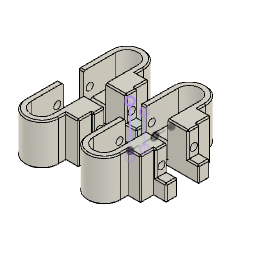
triangle_lab_filament_sensor_mount (Autodesk Fusion 360 design; units mm, degrees)
Autodesk Fusion 360 part; units mm, degrees
sketch "Primary" plane through (0, 0, 0) normal (0, 1, 0) x (1, 0, 0) in component "triangle_lab_filament_sensor_mount_a"
  line L0 (0, 0) -> (16, 0)
  line L1 (16, 0) -> (16, -23.5)
  line L2 (16, -23.5) -> (0, -23.5)
  line L3 (0, -23.5) -> (0, 0)
  line L4 (16, -12) -> (22, -12)
  line L5 (22, -12) -> (22, 0)
  line L6 (22, 0) -> (16, 0)
  line L7 (16, 0) -> (16, -12)
  line L8 (8, -23.5) -> (8, 0) construction
  circle A0 centre (8, -15.5) radius 5.3
  circle A1 centre (8, -15.5) radius 8
  line L9 (22, 0) -> (28, 0)
  line L10 (28, 0) -> (28, -5.6)
  line L11 (28, -5.6) -> (22, -5.6)
  line L12 (22, -5.6) -> (22, 0)
  line L13 (2.7, -15.5) -> (2.7, 0)
  line L14 (13.3, -15.5) -> (13.3, 0)
  line L15 (23, -5.6) -> (23, 0)
  line L16 (8, -20.8) -> (16, -20.8) construction
  line L17 (13.3, -2.8) -> (0, -2.8) construction
  line L18 (2.7, -17.4) -> (13.3, -17.4) construction
  circle A2 centre (8, -17.4) radius 2.1
  circle A3 centre (8, -17.4) radius 4.8
  dimension "d1" = 16
  dimension "d3" = 12
  dimension "d4" = 6
  dimension "d5" = 10.6
  dimension "d6" = 5.6
  dimension "d7" = 6
  dimension "d28" = 9.4
  dimension "d41" = 1
  dimension "d54" = 18
  dimension "d55" = 2.8
  dimension "d57" = 3.4
  dimension "d58" = 4.2
  dimension "d62" = 9.6
  constraint horizontal L0
  constraint vertical L1
  constraint horizontal L2
  constraint vertical L3
  constraint coincident L0.start L3.end
  constraint horizontal L4
  constraint vertical L5
  constraint horizontal L6
  constraint vertical L7
  constraint coincident L1 L4.start
  constraint collinear L0 L6
  constraint midpoint L2 L8.start
  constraint midpoint L0 L8.end
  constraint coincident L8 A0.centre
  constraint tangent L3 A1
  constraint tangent L2 A1
  constraint tangent L1 A1
  constraint horizontal L9
  constraint vertical L10
  constraint horizontal L11
  constraint vertical L12
  constraint coincident A0 L13.start
  constraint coincident L0 L13.end
  constraint tangent A0 L13
  constraint coincident A0 L14.start
  constraint coincident L0 L14.end
  constraint perpendicular L0 L14
  constraint perpendicular L0 L13
  constraint tangent A0 L14
  constraint coincident L11 L15.start
  constraint coincident L9 L15.end
  constraint perpendicular L9 L15
  constraint coincident A0 L16.start
  constraint coincident L8 L16.start
  constraint coincident L1 L16.end
  constraint tangent A0 L16
  constraint coincident A0.centre A1.centre
  constraint coincident L14 L17.start
  constraint coincident L3 L17.end
  constraint perpendicular L3 L17
  constraint coincident L13 L18.start
  constraint coincident L14 L18.end
  constraint perpendicular L14 L18
  constraint midpoint L18 A2.centre
  constraint concentric A2 A3
  measures "d1" distance of L0.start L0.end
  measures "d3" distance of L4.end L5.end
  measures "d4" distance of L5.end L0.end
  measures "d5" diameter of A0
  measures "d6" distance of L9.end L10.end
  measures "d7" distance of L5.end L9.end
  measures "d41" distance of L5 L15
  measures "d54" distance of L16 L17
  measures "d55" distance of L0 L17
  measures "d57" distance of L16 L18
  measures "d58" diameter of A2
  measures "d62" diameter of A3
extrude "Extrude1" add sketch "Primary" along normal blind 20 contours L0 L3 A1 L13 | L0 A1 L13 L14 | A0 A1 L13 L14 A3 | L0 L1 L7 A1 L14 | A0 A1 L13 L14 | L1 L4 L5 L6 L7 L12 | A0 A3 | A0 A3 | A0 A3 | A2 makes body 1 in component "triangle_lab_filament_sensor_mount_a"
extrude "Extrude4" add sketch "Primary" along normal blind 8 contours L5 L9 L11 L12 L15 | L9 L10 L11 L15 bodies 1 in component "triangle_lab_filament_sensor_mount_a"
extrude "Extrude8" add sketch "Primary" along normal up to surface (12 mm away) from surface at 8 contours L5 L9 L11 L12 L15 bodies 1 in component "triangle_lab_filament_sensor_mount_a"
extrude "Extrude2" cut sketch "Primary" along normal up to surface (13 mm away) from surface at 7 contours L0 A1 L13 L14 | A0 A1 L13 L14 | A0 A3 | A0 A3 | A2 picked at (8.6958, -11.0584) picked at (11.7721, -17.7848) bodies 1 in component "triangle_lab_filament_sensor_mount_a"
extrude "Extrude3" cut sketch "Primary" along normal up to surface (7 mm away) contours A2 bodies 1 in component "triangle_lab_filament_sensor_mount_a"
sketch "Sketch4" plane through (0, 0, 0) normal (-1, 0, 0) x (0, -1, 0) in component "triangle_lab_filament_sensor_mount_a"
  line L0 (0, 0) -> (0, 15.5)
  line L1 (0, 15.5) -> (-20, 15.5)
  line L2 (-20, 15.5) -> (-20, 0)
  line L3 (-20, 0) -> (0, 0)
  circle A0 centre (-12, 2.8) radius 1.7
  line L4 (0, 23.5) -> (0, 0)
  line L5 (-7, 15.5) -> (-7, 0)
  line L6 (0, 2.8) -> (-20, 2.8) construction
  point P0 (0, 2.8)
  dimension "d37" = 3.4
  dimension "d40" = 5
  constraint coincident P0 L6.start
  constraint coincident L2 L6.end
  constraint perpendicular L2 L6
  constraint coincident A0.centre L6
  measures "d37" diameter of A0
  measures "d40" distance of A0.centre L5
extrude "Extrude7" cut sketch "Sketch4" against normal up to surface (28 mm away) contours A0 bodies 1 in component "triangle_lab_filament_sensor_mount_a"
chamfer "Chamfer4" distance 4 angle 45 1 edges at (8, 7, 0) on bodies 1 in component "triangle_lab_filament_sensor_mount_a"
chamfer "Chamfer3" distance 0.6 angle 45 26 edges at (16, 0, 13.75) (8, 0, 23.5) (0, 0, 7.75) (19, 0, 12) (22, 0, 8.8) (25, 0, 5.6) (28, 0, 2.8) (22, 10, 12) (0, 20, 7.75) (8, 20, 23.5) (16, 20, 13.75) (19, 20, 12) (22, 20, 8.8) (23, 20, 2.8) (18.15, 20, 0) (1.35, 20, 0) (23, 14, 5.6) (28, 4, 5.6) (25.5, 8, 5.6) (28, 8, 2.8) (28, 4, 0) (25.5, 8, 0) (23, 14, 0) (0, 10, 0) (14, 0, 0) (22.5, 20, 5.6) on bodies 1 in component "triangle_lab_filament_sensor_mount_a"
copy_body "CopyPasteBodies1" bodies 1 makes body 2 in component "triangle_lab_filament_sensor_mount_b"
move_body "Move1" bodies 2 to x (1, 0, 0) y (0, 1, 0) z (0, 0, 1) at (-30, 0, 0) in component "triangle_lab_filament_sensor_mount_b"
extrude "Extrude10" cut sketch "Primary" along normal up to surface (7 mm away) contours A0 A3 | A0 A3 picked at (11.7721, -17.7848) picked at (9.2091, -21.1089) bodies 1 in component "triangle_lab_filament_sensor_mount_a"
fillet "Fillet4" radius 1.3 1 faces at (6.7909, 7, 21.1089) on bodies 1 in component "triangle_lab_filament_sensor_mount_a"
move_body "Move2" bodies 1 to x (1, 0, 0) y (0, 0, 1) z (0, -1, 0) at (0, -5, 0) in component "triangle_lab_filament_sensor_mount_a"
mirror "Mirror2" about plane through (0, 0, 0) normal (0, 1, 0) of bodies 1 makes body 3 in component "triangle_lab_filament_sensor_mount_a"
move_body "Move2'" bodies 2 to x (1, 0, 0) y (0, 0, 1) z (0, -1, 0) at (0, -5, 0) in component "triangle_lab_filament_sensor_mount_b"
mirror "Mirror1" about plane through (0, 0, 0) normal (0, 1, 0) of bodies 2 makes body 4 in component "triangle_lab_filament_sensor_mount_b"
component "triangle_lab_filament_sensor_mount_a" placed x (1, 0, 0) y (0, 1, 0) z (0, 0, 1) at (0, 0, 0)
component "triangle_lab_filament_sensor_mount_b" placed x (1, 0, 0) y (0, 1, 0) z (0, 0, 1) at (0, 0, 0)
named bodies: "Mount_A_1", "Mount_B_1", "Mount_A_2", "Mount_B_2"
